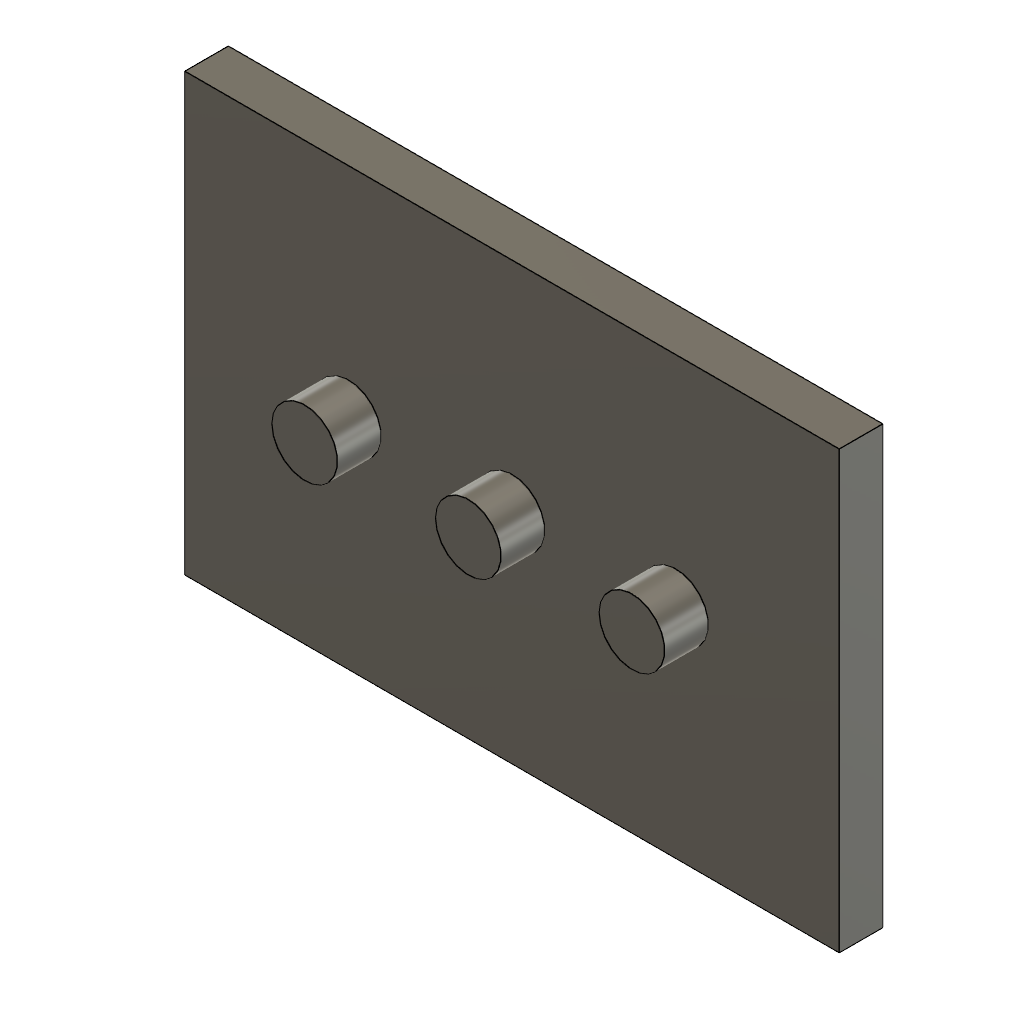
pat_rect_symmetric (Autodesk Fusion 360 design; units mm, degrees)
part number: 2026-11-13-14-45-14-949
Autodesk Fusion 360 part; units mm, degrees
sketch "Sketch1" plane through (0, 0, 0) normal (0, 0, 1) x (1, 0, 0)
  line L0 (-30, -20) -> (30, -20)
  line L1 (30, -20) -> (30, 20)
  line L2 (30, 20) -> (-30, 20)
  line L3 (-30, 20) -> (-30, -20)
extrude "Extrude1" add sketch "Sketch1" along normal blind 4
sketch "Sketch2" plane through (0, 0, 4) normal (0, 0, 1) x (1, 0, 0)
  line L0 (-30, 20) -> (-30, -20)
  line L1 (-30, -20) -> (30, -20)
  line L2 (30, -20) -> (30, 20)
  line L3 (30, 20) -> (-30, 20)
  circle A0 centre (0, 0) radius 3
extrude "Extrude2" add sketch "Sketch2" along normal blind 4 contours A0
pattern_linear "R-Pattern1" count 3 spacing 15 along (1, 0, 0) both ways count 3 spacing 0 along (1, 0, 0) of "Extrude2"
